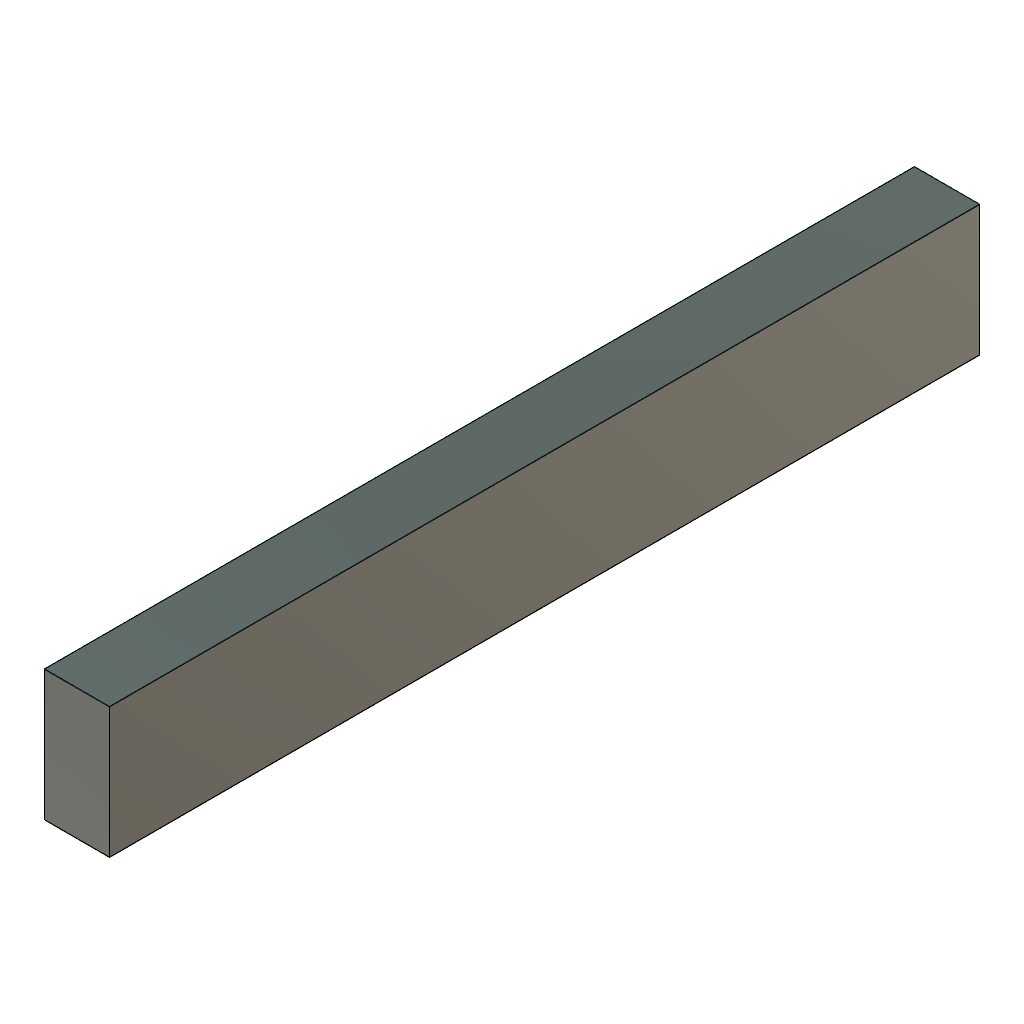
Machine_Design_Lab_3 (Autodesk Fusion 360 design; units mm, degrees)
part number: 2026-09-17-17-29-20-655
Autodesk Fusion 360 part; units mm, degrees
sketch "Sketch1" plane through (0, 0, 0) normal (0, 1, 0) x (1, 0, 0)
  line L0 (0, 0) -> (0, -38.1)
  line L1 (0, -38.1) -> (19.05, -38.1)
  line L2 (19.05, -38.1) -> (19.05, 0)
  line L3 (19.05, 0) -> (0, 0)
  dimension "d1" = 19.05
  constraint coincident L0.start L3.end
  constraint vertical L0
  constraint perpendicular L0 L1
  constraint perpendicular L1 L2
  constraint perpendicular L0 L3
  measures "d1" distance of L0.end L1.end
extrude "Extrude1" add sketch "Sketch1" along normal blind 254
sketch "Sketch2" plane through (0, 0, 38.1) normal (0, 0, 1) x (-1, 0, 0)
  line L0 (0, 0) -> (-19.05, 0)
  line L1 (-19.05, 0) -> (-19.05, -254)
  line L2 (-19.05, -254) -> (0, -254)
  line L3 (0, -254) -> (0, 0)
